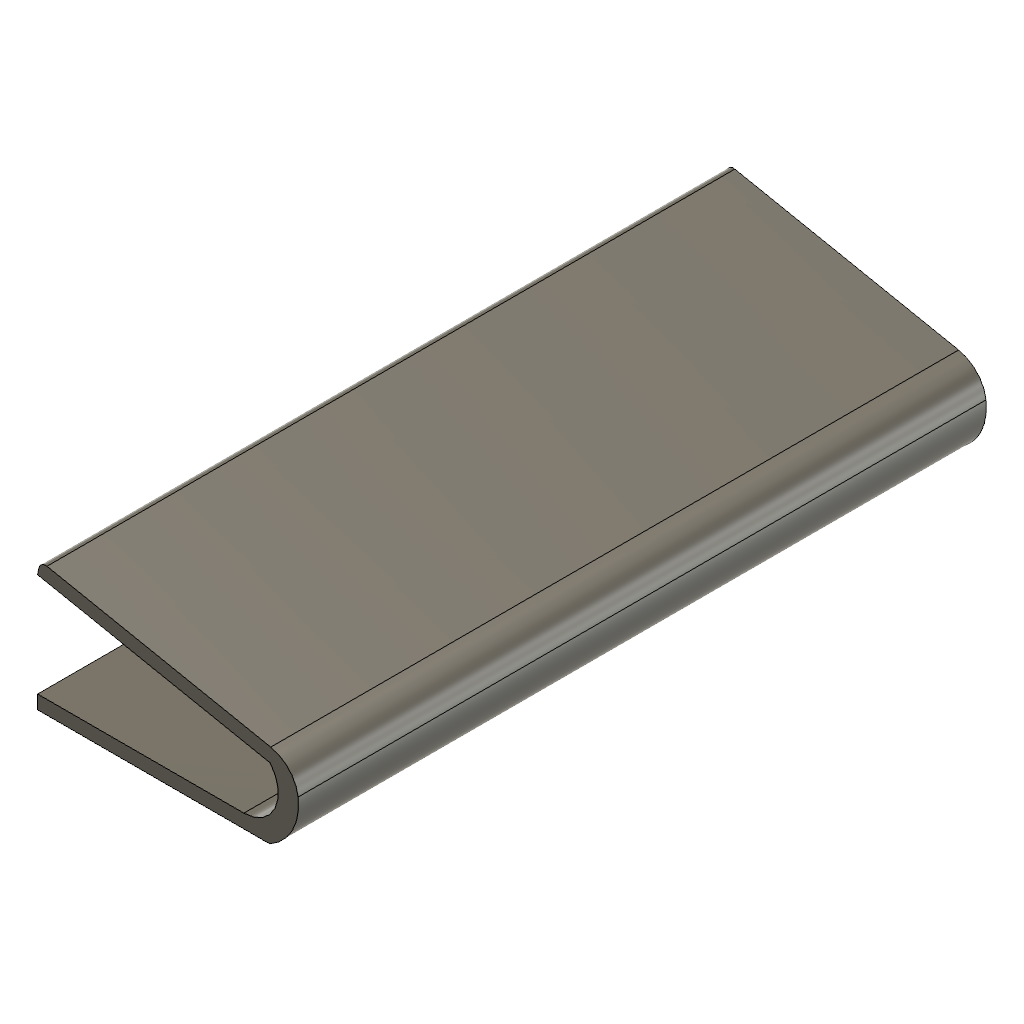
rc-airplanes-trainer-airplane-fusion-parts-wing-band-clip-front (Autodesk Fusion 360 design; units mm, degrees)
Autodesk Fusion 360 part; units mm, degrees
sketch "Sketch1" plane through (0, 0, 0) normal (0, 0, 1) x (1, 0, 0)
  line L0 (-17.3341, 1.151) -> (12.6659, 1.151)
  line L1 (-17.3341, 1.151) -> (7.6659, 1.151)
  line L2 (-17.3341, 16.151) -> (7.6659, 11.151)
  line L3 (7.6659, 11.151) -> (16.4758, 9.389)
  arc A0 (12.6659, 1.151) -> (16.4758, 9.389) centre (12.6659, 6.151) ccw
  line L4 (-17.3341, 1.151) -> (-17.3341, -0.849)
  line L5 (-17.3341, 16.151) -> (-17.138, 17.1316)
  line L6 (-15.9613, 17.916) -> (16.5641, 11.411)
  line L7 (-17.3341, -0.849) -> (16.412, -0.849)
  arc A1 (16.412, -0.849) -> (20.5464, 7.1155) centre (12.6659, 6.151) ccw
  arc A2 (20.5464, 7.1155) -> (16.5641, 11.411) centre (15.5835, 6.5081) ccw
  arc A3 (-15.9613, 17.916) -> (-17.138, 17.1316) centre (-16.1574, 16.9354) ccw
  point P0 (-16.9418, 18.1121)
  dimension "d10" = 30
  dimension "d11" = 25
  dimension "d12" = 10
  dimension "d13" = 15
  dimension "d14" = 2
  dimension "d15" = 2
  dimension "d16" = 5
  dimension "d17" = 1
  constraint horizontal L0
  constraint parallel L0 L1
  constraint tangent L0 A0
  constraint parallel L2 L3
  constraint perpendicular L0 L4
  constraint perpendicular L2 L5
  constraint perpendicular L5 L6
  constraint perpendicular L4 L7
  constraint concentric A0 A1
  constraint tangent A1 A2
  constraint tangent L6 A2
  constraint coincident P0 L5
  constraint coincident P0 L6
  constraint tangent L5 A3
  constraint tangent L6 A3
  measures "d10" distance of L0.start L0.end
  measures "d11" distance of L0.start L1.end
  measures "d12" distance of L1.end L2.end
  measures "d13" distance of L0.start L2.start
  measures "d14" distance of L0.start L4.end
  measures "d15" distance of L2.start P0
  measures "d16" radius of A2
  measures "d17" radius of A3
extrude "Extrude1" add sketch "Sketch1" along normal blind 90
extrude "Extrude2" add 1 faces at (2.2479, -0.1823, 90) along direction (0, 0, 1) blind 60
extrude "Extrude3" cut 1 faces at (3.9146, -0.1823, 150) along direction (0, 0, -1) blind 50
